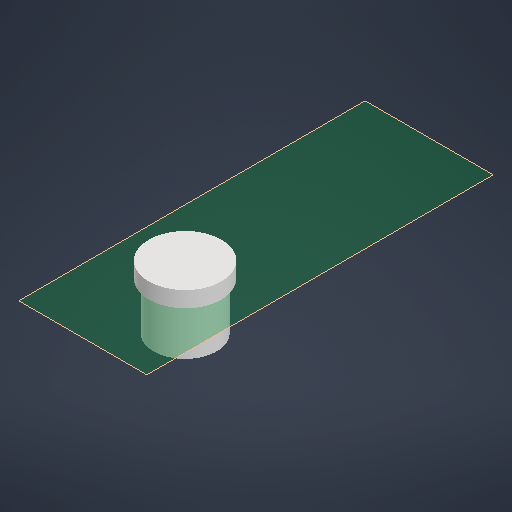
# Autodesk Inventor part: bouton
Saved by Autodesk Inventor 2026.1 (Build 301233020, 233B)
## iProperties
Created: 2025-12-18
Part Number: bouton
Material: Générique
Document SubType Name: Modeling
Designer: matpo
Density: 1 g/cm^3
Appearance: Par défaut
Author: matpo
Autodesk Inventor part; units mm, degrees
ref_plane "YZ Plane" through (0, 0, 0) normal (1, 0, 0) x (0, 1, 0)
ref_plane "XZ Plane" through (0, 0, 0) normal (0, 1, 0) x (-1, 0, 0)
ref_plane "XY Plane" through (0, 0, 0) normal (0, 0, 1) x (1, 0, 0)
ref_plane "Plan de construction1" through (56.5355, 49.4968, 11.6826) normal (0, -1, 0) x (-1, 0, 0)
sketch "Esquisse1" plane through (56.5355, 49.4968, 11.6826) normal (0, -1, 0) x (-1, 0, 0)
  circle A0 centre (3.7, -14.5) radius 2.5 projected
  circle A1 centre (3.7, -14.5) radius 2
  circle A2 centre (3.7, -14.5) radius 1.6
  point P0 (56.5355, 11.6826)
  dimension "d2" = 0.4
  dimension "d3" = 3.2
  constraints: 2 centre point
  measures "d2" radial gap between concentric circles of A1 A2
  measures "d3" diameter of A2
extrude "Extrusion1" add sketch "Esquisse1" along normal blind 3 contours A1
sketch "Esquisse2" plane through (52.8355, 49.4968, 26.1826) normal (0, 1, 0) x (1, 0, 0)
  circle A0 centre (0, 0) radius 2 projected
  circle A1 centre (0, 0) radius 2.3
  point P0 (-52.8355, 26.1826)
  dimension "d8" = 0.3
  constraints: 1 centre point
  measures "d8" radial gap between concentric circles of A0 A1
extrude "Extrusion2" add sketch "Esquisse2" along normal blind 1 contours A0 | A1
